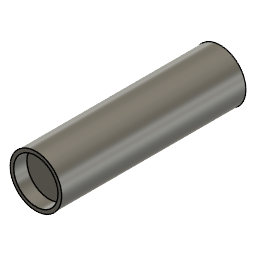
wdd2-pick-and-place-arm (Autodesk Fusion 360 archive; units mm, degrees)
design "Pin-11/9/26"
part number: 2026-09-11-17-14-21-414
Autodesk Fusion 360 part; units mm, degrees
sketch "Sketch1" plane through (0, 0, 0) normal (0, 0, 1) x (1, 0, 0)
  circle A0 centre (0, 0) radius 3.9
  dimension "d1" = 7.8
  constraint coincident A0.centre origin
  measures "d1" diameter of A0
extrude "Extrude1" add sketch "Sketch1" along normal blind 13
sketch "Sketch2" plane through (0, 0, 13) normal (0, 0, 1) x (1, 0, 0)
  circle A0 centre (0, 0) radius 3.9
  circle A1 centre (0, 0) radius 3.9
  constraint concentric A0 A1
extrude "Extrude2" add sketch "Sketch2" along normal blind 14.85
sketch "Sketch3" plane through (0, 0, 27.85) normal (0, 0, 1) x (1, 0, 0)
  circle A0 centre (0, 0) radius 3.9
  circle A1 centre (0, 0) radius 3.35
  dimension "d6" = 6.7
  constraint concentric A0 A1
  measures "d6" diameter of A1
extrude "Extrude3" cut sketch "Sketch3" against normal blind 2 contours A1
equation "d4 = 17 mm - 2.15 mm"

design "Pin-11/9/26"
part number: 2026-09-11-17-14-21-414
Autodesk Fusion 360 part; units mm, degrees
sketch "Sketch1" plane through (0, 0, 0) normal (0, 0, 1) x (1, 0, 0)
  circle A0 centre (0, 0) radius 3.9
  dimension "d1" = 7.8
  constraint coincident A0.centre origin
  measures "d1" diameter of A0
extrude "Extrude1" add sketch "Sketch1" along normal blind 13
sketch "Sketch2" plane through (0, 0, 13) normal (0, 0, 1) x (1, 0, 0)
  circle A0 centre (0, 0) radius 3.9
  circle A1 centre (0, 0) radius 3.9
  constraint concentric A0 A1
extrude "Extrude2" add sketch "Sketch2" along normal blind 14.85
sketch "Sketch3" plane through (0, 0, 27.85) normal (0, 0, 1) x (1, 0, 0)
  circle A0 centre (0, 0) radius 3.9
  circle A1 centre (0, 0) radius 3.35
  dimension "d6" = 6.7
  constraint concentric A0 A1
  measures "d6" diameter of A1
extrude "Extrude3" cut sketch "Sketch3" against normal blind 2 contours A1
sketch "Sketch4" plane through (0, 0, 25.85) normal (0, 0, 1) x (1, 0, 0)
  circle A0 centre (0, 0) radius 3.35
  circle A1 centre (0, 0) radius 2.5
  dimension "d9" = 5
  constraint coincident A0.centre A1.centre
  measures "d9" diameter of A1
extrude "Extrude4" add sketch "Sketch4" along normal blind 2
chamfer "Chamfer1" distance 0.4 angle 45 1 edges at (-2.3308, 0.904, 27.85) tangent chain off
fillet "Fillet1" radius 0.4 2 edges at (-3.6361, -1.4103, 27.85) (-3.6361, -1.4103, 0)
sketch "Sketch5" plane through (0, 0, 27.85) normal (0, 0, 1) x (1, 0, 0)
  circle A0 centre (0, 0) radius 2.9
  circle A1 centre (0, 0) radius 3.5
  circle A2 centre (0, 0) radius 3.9
  circle A3 centre (0, 0) radius 2.9
  line L0 (-2.6077, -2.9) -> (2.6077, -2.9)
  dimension "d15" = -1
  constraint horizontal L0
  constraint tangent A3 L0
  constraint coincident A2 L0.start
  constraint coincident A2 L0.end
extrude "Extrude5" cut sketch "Sketch5" against normal blind 27.85 contours A1 L0 | A1 A2 L0 picked at (-0.1727, -3.2871) picked at (2.2413, -3.0165)
equation "d4 = 17 mm - 2.15 mm"
